Autodesk Fusion 360 part; units mm, degrees
(part 2 of 8)
sketch "B Facet 45 Triangle 2" plane through (0, 53.033, 53.033) normal (0, 0.707107, 0.707107) x (1, 0, 0) in component "B Moving Body"
  line L0 (-43.7939, -27.066) -> (-124, 27.066) construction
  line L1 (-124, 27.066) -> (-124, -27.066) construction
  line L2 (-124, -27.066) -> (-43.7939, -27.066) construction
  line L3 (-56.8709, -23.066) -> (-120, 19.5406)
  line L4 (-120, 19.5406) -> (-120, -23.066)
  line L5 (-120, -23.066) -> (-56.8709, -23.066)
  dimension "d369" = 43.7939
  dimension "d370" = 27.066
  dimension "d371" = 124
  dimension "d372" = 27.066
  dimension "d373" = 124
  dimension "d374" = 27.066
  dimension "d375" = -4
  measures "d369" horizontal distance of origin L0.start
  measures "d370" vertical distance of origin L0.start
  measures "d371" horizontal distance of origin L0.end
  measures "d372" vertical distance of origin L0.end
  measures "d373" horizontal distance of origin L1.end
  measures "d374" vertical distance of origin L1.end
extrude "B Facet 45 Opening 2" cut sketch "B Facet 45 Triangle 2" against normal blind 4.7 bodies 4 in component "B Moving Body"
fillet "B Facet 45 Aperture Root Radii" radius 1.5 6 edges at (-120, 35.1319, 67.7522) (-56.8709, 35.1319, 67.7522) (-120, 65.2593, 37.6247) (-110.9231, 67.7522, 35.1319) (-59.6927, 43.3032, 59.5808) (-84.1416, 67.7522, 35.1319) on bodies 4 in component "B Moving Body"
ref_plane "WorkPlane5" through (12.125, 0, 0) normal (0, 0, 1) x (1, 0, 0) in component "B Moving Body"
ref_plane "WorkPlane6" through (12.125, 0, 75) normal (0, 0, 1) x (1, 0, 0) in component "B Moving Body"
sketch "B Facet 90 Triangle 1" plane through (0, 0, 75) normal (0, 0, 1) x (1, 0, 0) in component "B Moving Body"
  line L0 (17.1665, -27.066) -> (-36.9655, 27.066) construction
  line L1 (-36.9655, 27.066) -> (-53.4167, -27.066) construction
  line L2 (-53.4167, -27.066) -> (17.1665, -27.066) construction
  line L3 (7.5097, -23.066) -> (-35.0777, 19.5214)
  line L4 (-35.0777, 19.5214) -> (-48.0205, -23.066)
  line L5 (-48.0205, -23.066) -> (7.5097, -23.066)
  dimension "d384" = 17.1665
  dimension "d385" = 27.066
  dimension "d386" = 36.9655
  dimension "d387" = 27.066
  dimension "d388" = 53.4167
  dimension "d389" = 27.066
  dimension "d390" = -4
  measures "d384" horizontal distance of origin L0.start
  measures "d385" vertical distance of origin L0.start
  measures "d386" horizontal distance of origin L0.end
  measures "d387" vertical distance of origin L0.end
  measures "d388" horizontal distance of origin L1.end
  measures "d389" vertical distance of origin L1.end
extrude "B Facet 90 Opening 1" cut sketch "B Facet 90 Triangle 1" against normal blind 4.7 bodies 4 in component "B Moving Body"
sketch "B Facet 90 Triangle 2" plane through (0, 0, 75) normal (0, 0, 1) x (1, 0, 0) in component "B Moving Body"
  line L0 (-36.9655, 27.066) -> (-53.4167, -27.066) construction
  line L1 (-53.4167, -27.066) -> (-124, 27.066) construction
  line L2 (-124, 27.066) -> (-36.9655, 27.066) construction
  line L3 (-42.3618, 23.066) -> (-55.5648, -20.3777)
  line L4 (-55.5648, -20.3777) -> (-112.2115, 23.066)
  line L5 (-112.2115, 23.066) -> (-42.3618, 23.066)
  dimension "d393" = 36.9655
  dimension "d394" = 27.066
  dimension "d395" = 53.4167
  dimension "d396" = 27.066
  dimension "d397" = 124
  dimension "d398" = 27.066
  dimension "d399" = 4
  measures "d393" horizontal distance of origin L0.start
  measures "d394" vertical distance of origin L0.start
  measures "d395" horizontal distance of origin L0.end
  measures "d396" vertical distance of origin L0.end
  measures "d397" horizontal distance of origin L1.end
  measures "d398" vertical distance of origin L1.end
extrude "B Facet 90 Opening 2" cut sketch "B Facet 90 Triangle 2" against normal blind 4.7 bodies 4 in component "B Moving Body"
sketch "B Facet 90 Triangle 3" plane through (0, 0, 75) normal (0, 0, 1) x (1, 0, 0) in component "B Moving Body"
  line L0 (-53.4167, -27.066) -> (-124, 27.066) construction
  line L1 (-124, 27.066) -> (-124, -27.066) construction
  line L2 (-124, -27.066) -> (-53.4167, -27.066) construction
  line L3 (-65.2053, -23.066) -> (-120, 18.9574)
  line L4 (-120, 18.9574) -> (-120, -23.066)
  line L5 (-120, -23.066) -> (-65.2053, -23.066)
  dimension "d402" = 53.4167
  dimension "d403" = 27.066
  dimension "d404" = 124
  dimension "d405" = 27.066
  dimension "d406" = 124
  dimension "d407" = 27.066
  dimension "d408" = -4
  measures "d402" horizontal distance of origin L0.start
  measures "d403" vertical distance of origin L0.start
  measures "d404" horizontal distance of origin L0.end
  measures "d405" vertical distance of origin L0.end
  measures "d406" horizontal distance of origin L1.end
  measures "d407" vertical distance of origin L1.end
extrude "B Facet 90 Opening 3" cut sketch "B Facet 90 Triangle 3" against normal blind 4.7 bodies 4 in component "B Moving Body"
fillet "B Facet 90 Aperture Root Radii" radius 1.5 9 edges at (-120, -23.066, 72.75) (-65.2053, -23.066, 72.75) (-120, 18.9574, 72.75) (-112.2115, 23.066, 72.75) (-55.5648, -20.3777, 72.75) (-42.3618, 23.066, 72.75) (-48.0205, -23.066, 72.75) (7.5097, -23.066, 72.75) (-35.0777, 19.5214, 72.75) on bodies 4 in component "B Moving Body"
ref_plane "WorkPlane7" through (12.125, 0, 0) normal (0, -0.707107, 0.707107) x (1, 0, 0) in component "B Moving Body"
ref_plane "WorkPlane8" through (12.125, -53.033, 53.033) normal (0, -0.707107, 0.707107) x (1, 0, 0) in component "B Moving Body"
sketch "B Facet 135 Triangle 1" plane through (0, -53.033, 53.033) normal (0, -0.707107, 0.707107) x (1, 0, 0) in component "B Moving Body"
  line L0 (23.9949, 27.066) -> (62.2721, -27.066) construction
  line L1 (62.2721, -27.066) -> (-25.3367, 27.066) construction
  line L2 (-25.3367, 27.066) -> (23.9949, 27.066) construction
  line L3 (21.9244, 23.066) -> (47.6674, -13.34)
  line L4 (47.6674, -13.34) -> (-11.2532, 23.066)
  line L5 (-11.2532, 23.066) -> (21.9244, 23.066)
  dimension "d417" = 23.9949
  dimension "d418" = 27.066
  dimension "d419" = 62.2721
  dimension "d420" = 27.066
  dimension "d421" = 25.3367
  dimension "d422" = 27.066
  dimension "d423" = 4
  measures "d417" horizontal distance of origin L0.start
  measures "d418" vertical distance of origin L0.start
  measures "d419" horizontal distance of origin L0.end
  measures "d420" vertical distance of origin L0.end
  measures "d421" horizontal distance of origin L1.end
  measures "d422" vertical distance of origin L1.end
extrude "B Facet 135 Opening 1" cut sketch "B Facet 135 Triangle 1" against normal blind 4.7 bodies 4 in component "B Moving Body"
sketch "B Facet 135 Triangle 2" plane through (0, -53.033, 53.033) normal (0, -0.707107, 0.707107) x (1, 0, 0) in component "B Moving Body"
  line L0 (62.2721, -27.066) -> (-25.3367, 27.066) construction
  line L1 (-25.3367, 27.066) -> (-61.9093, -27.066) construction
  line L2 (-61.9093, -27.066) -> (62.2721, -27.066) construction
  line L3 (48.1886, -23.066) -> (-24.1722, 21.6445)
  line L4 (-24.1722, 21.6445) -> (-54.3795, -23.066)
  line L5 (-54.3795, -23.066) -> (48.1886, -23.066)
  dimension "d426" = 62.2721
  dimension "d427" = 27.066
  dimension "d428" = 25.3367
  dimension "d429" = 27.066
  dimension "d430" = 61.9093
  dimension "d431" = 27.066
  dimension "d432" = -4
  measures "d426" horizontal distance of origin L0.start
  measures "d427" vertical distance of origin L0.start
  measures "d428" horizontal distance of origin L0.end
  measures "d429" vertical distance of origin L0.end
  measures "d430" horizontal distance of origin L1.end
  measures "d431" vertical distance of origin L1.end
extrude "B Facet 135 Opening 2" cut sketch "B Facet 135 Triangle 2" against normal blind 4.7 bodies 4 in component "B Moving Body"
sketch "B Facet 135 Triangle 3" plane through (0, -53.033, 53.033) normal (0, -0.707107, 0.707107) x (1, 0, 0) in component "B Moving Body"
  line L0 (-25.3367, 27.066) -> (-61.9093, -27.066) construction
  line L1 (-61.9093, -27.066) -> (-124, 27.066) construction
  line L2 (-124, 27.066) -> (-25.3367, 27.066) construction
  line L3 (-32.8665, 23.066) -> (-62.6909, -21.0779)
  line L4 (-62.6909, -21.0779) -> (-113.325, 23.066)
  line L5 (-113.325, 23.066) -> (-32.8665, 23.066)
  dimension "d435" = 25.3367
  dimension "d436" = 27.066
  dimension "d437" = 61.9093
  dimension "d438" = 27.066
  dimension "d439" = 124
  dimension "d440" = 27.066
  dimension "d441" = 4
  measures "d435" horizontal distance of origin L0.start
  measures "d436" vertical distance of origin L0.start
  measures "d437" horizontal distance of origin L0.end
  measures "d438" vertical distance of origin L0.end
  measures "d439" horizontal distance of origin L1.end
  measures "d440" vertical distance of origin L1.end
extrude "B Facet 135 Opening 3" cut sketch "B Facet 135 Triangle 3" against normal blind 4.7 bodies 4 in component "B Moving Body"
sketch "B Facet 135 Triangle 4" plane through (0, -53.033, 53.033) normal (0, -0.707107, 0.707107) x (1, 0, 0) in component "B Moving Body"
  line L0 (-61.9093, -27.066) -> (-124, 27.066) construction
  line L1 (-124, 27.066) -> (-124, -27.066) construction
  line L2 (-124, -27.066) -> (-61.9093, -27.066) construction
  line L3 (-72.5843, -23.066) -> (-120, 18.272)
  line L4 (-120, 18.272) -> (-120, -23.066)
  line L5 (-120, -23.066) -> (-72.5843, -23.066)
  dimension "d444" = 61.9093
  dimension "d445" = 27.066
  dimension "d446" = 124
  dimension "d447" = 27.066
  dimension "d448" = 124
  dimension "d449" = 27.066
  dimension "d450" = -4
  measures "d444" horizontal distance of origin L0.start
  measures "d445" vertical distance of origin L0.start
  measures "d446" horizontal distance of origin L0.end
  measures "d447" vertical distance of origin L0.end
  measures "d448" horizontal distance of origin L1.end
  measures "d449" vertical distance of origin L1.end
extrude "B Facet 135 Opening 4" cut sketch "B Facet 135 Triangle 4" against normal blind 4.7 bodies 4 in component "B Moving Body"
fillet "B Facet 135 Aperture Root Radii" radius 1.5 12 edges at (-120, -67.7522, 35.1319) (-72.5843, -67.7522, 35.1319) (-120, -38.5218, 64.3623) (-113.325, -35.1319, 67.7522) (-62.6909, -66.3463, 36.5377) (-32.8665, -35.1319, 67.7522) (-54.3795, -67.7522, 35.1319) (48.1886, -67.7522, 35.1319) (-24.1722, -36.137, 66.747) (-11.2532, -35.1319, 67.7522) (47.6674, -60.8748, 42.0092) (21.9244, -35.1319, 67.7522) on bodies 4 in component "B Moving Body"
ref_plane "WorkPlane9" through (12.125, 0, 0) normal (0, -1, 0) x (1, 0, 0) in component "B Moving Body"
ref_plane "WorkPlane10" through (12.125, -75, 0) normal (0, -1, 0) x (1, 0, 0) in component "B Moving Body"
sketch "B Facet 180 Triangle 1" plane through (0, -75, 0) normal (0, -1, 0) x (-1, 0, 0) in component "B Moving Body"
  line L0 (-65.1005, -27.066) -> (-65.1005, 27.066) construction
  line L1 (-65.1005, 27.066) -> (-2.067, -27.066) construction
  line L2 (-2.067, -27.066) -> (-65.1005, -27.066) construction
  line L3 (-61.1005, -23.066) -> (-61.1005, 18.3583)
  line L4 (-61.1005, 18.3583) -> (-12.8644, -23.066)
  line L5 (-12.8644, -23.066) -> (-61.1005, -23.066)
  dimension "d459" = 65.1005
  dimension "d460" = 27.066
  dimension "d461" = 65.1005
  dimension "d462" = 27.066
  dimension "d463" = 2.067
  dimension "d464" = 27.066
  dimension "d465" = 4
  measures "d459" horizontal distance of origin L0.start
  measures "d460" vertical distance of origin L0.start
  measures "d461" horizontal distance of origin L0.end
  measures "d462" vertical distance of origin L0.end
  measures "d463" horizontal distance of origin L1.end
  measures "d464" vertical distance of origin L1.end
extrude "B Facet 180 Opening 1" cut sketch "B Facet 180 Triangle 1" against normal blind 4.7 bodies 4 in component "B Moving Body"
sketch "B Facet 180 Triangle 2" plane through (0, -75, 0) normal (0, -1, 0) x (-1, 0, 0) in component "B Moving Body"
  line L0 (-65.1005, 27.066) -> (-2.067, -27.066) construction
  line L1 (-2.067, -27.066) -> (60.9665, 27.066) construction
  line L2 (60.9665, 27.066) -> (-65.1005, 27.066) construction
  line L3 (-54.3031, 23.066) -> (-2.067, -21.7934)
  line L4 (-2.067, -21.7934) -> (50.1691, 23.066)
  line L5 (50.1691, 23.066) -> (-54.3031, 23.066)
  dimension "d468" = 65.1005
  dimension "d469" = 27.066
  dimension "d470" = 2.067
  dimension "d471" = 27.066
  dimension "d472" = 60.9665
  dimension "d473" = 27.066
  dimension "d474" = -4
  measures "d468" horizontal distance of origin L0.start
  measures "d469" vertical distance of origin L0.start
  measures "d470" horizontal distance of origin L0.end
  measures "d471" vertical distance of origin L0.end
  measures "d472" horizontal distance of origin L1.end
  measures "d473" vertical distance of origin L1.end
extrude "B Facet 180 Opening 2" cut sketch "B Facet 180 Triangle 2" against normal blind 4.7 bodies 4 in component "B Moving Body"
sketch "B Facet 180 Triangle 3" plane through (0, -75, 0) normal (0, -1, 0) x (-1, 0, 0) in component "B Moving Body"
  line L0 (-2.067, -27.066) -> (60.9665, 27.066) construction
  line L1 (60.9665, 27.066) -> (124, -27.066) construction
  line L2 (124, -27.066) -> (-2.067, -27.066) construction
  line L3 (8.7304, -23.066) -> (60.9665, 21.7934)
  line L4 (60.9665, 21.7934) -> (113.2026, -23.066)
  line L5 (113.2026, -23.066) -> (8.7304, -23.066)
  dimension "d477" = 2.067
  dimension "d478" = 27.066
  dimension "d479" = 60.9665
  dimension "d480" = 27.066
  dimension "d481" = 124
  dimension "d482" = 27.066
  dimension "d483" = 4
  measures "d477" horizontal distance of origin L0.start
  measures "d478" vertical distance of origin L0.start
  measures "d479" horizontal distance of origin L0.end
  measures "d480" vertical distance of origin L0.end
  measures "d481" horizontal distance of origin L1.end
  measures "d482" vertical distance of origin L1.end
extrude "B Facet 180 Opening 3" cut sketch "B Facet 180 Triangle 3" against normal blind 4.7 bodies 4 in component "B Moving Body"
sketch "B Facet 180 Triangle 4" plane through (0, -75, 0) normal (0, -1, 0) x (-1, 0, 0) in component "B Moving Body"
  line L0 (60.9665, 27.066) -> (124, -27.066) construction
  line L1 (124, -27.066) -> (124, 27.066) construction
  line L2 (124, 27.066) -> (60.9665, 27.066) construction
  line L3 (71.7639, 23.066) -> (120, -18.3583)
  line L4 (120, -18.3583) -> (120, 23.066)
  line L5 (120, 23.066) -> (71.7639, 23.066)
  dimension "d486" = 60.9665
  dimension "d487" = 27.066
  dimension "d488" = 124
  dimension "d489" = 27.066
  dimension "d490" = 124
  dimension "d491" = 27.066
  dimension "d492" = -4
  measures "d486" horizontal distance of origin L0.start
  measures "d487" vertical distance of origin L0.start
  measures "d488" horizontal distance of origin L0.end
  measures "d489" vertical distance of origin L0.end
  measures "d490" horizontal distance of origin L1.end
  measures "d491" vertical distance of origin L1.end
extrude "B Facet 180 Opening 4" cut sketch "B Facet 180 Triangle 4" against normal blind 4.7 bodies 4 in component "B Moving Body"
fillet "B Facet 180 Aperture Root Radii" radius 1.5 12 edges at (-120, -72.75, -23.066) (-71.7639, -72.75, -23.066) (-120, -72.75, 18.3583) (-113.2026, -72.75, 23.066) (-60.9665, -72.75, -21.7934) (-8.7304, -72.75, 23.066) (-50.1691, -72.75, -23.066) (54.3031, -72.75, -23.066) (2.067, -72.75, 21.7934) (12.8644, -72.75, 23.066) (61.1005, -72.75, -18.3583) (61.1005, -72.75, 23.066) on bodies 4 in component "B Moving Body"
ref_plane "WorkPlane11" through (12.125, 0, 0) normal (0, -0.707107, -0.707107) x (1, 0, 0) in component "B Moving Body"
ref_plane "WorkPlane12" through (12.125, -53.033, -53.033) normal (0, -0.707107, -0.707107) x (1, 0, 0) in component "B Moving Body"
sketch "B Facet 225 Triangle 1" plane through (0, -53.033, -53.033) normal (0, -0.707107, -0.707107) x (1, 0, 0) in component "B Moving Body"
  line L0 (62.2721, 27.066) -> (23.9949, -27.066) construction
  line L1 (23.9949, -27.066) -> (0.1814, 27.066) construction
  line L2 (0.1814, 27.066) -> (62.2721, 27.066) construction
  line L3 (54.5447, 23.066) -> (24.81, -18.9852)
  line L4 (24.81, -18.9852) -> (6.311, 23.066)
  line L5 (6.311, 23.066) -> (54.5447, 23.066)
  dimension "d501" = 62.2721
  dimension "d502" = 27.066
  dimension "d503" = 23.9949
  dimension "d504" = 27.066
  dimension "d505" = 0.1814
  dimension "d506" = 27.066
  dimension "d507" = 4
  measures "d501" horizontal distance of origin L0.start
  measures "d502" vertical distance of origin L0.start
  measures "d503" horizontal distance of origin L0.end
  measures "d504" vertical distance of origin L0.end
  measures "d505" horizontal distance of origin L1.end
  measures "d506" vertical distance of origin L1.end
extrude "B Facet 225 Opening 1" cut sketch "B Facet 225 Triangle 1" against normal blind 4.7 bodies 4 in component "B Moving Body"
sketch "B Facet 225 Triangle 2" plane through (0, -53.033, -53.033) normal (0, -0.707107, -0.707107) x (1, 0, 0) in component "B Moving Body"
  line L0 (23.9949, -27.066) -> (0.1814, 27.066) construction
  line L1 (0.1814, 27.066) -> (-74.6684, -27.066) construction
  line L2 (-74.6684, -27.066) -> (23.9949, -27.066) construction
  line L3 (17.8653, -23.066) -> (-1.4863, 20.9235)
  line L4 (-1.4863, 20.9235) -> (-62.3117, -23.066)
  line L5 (-62.3117, -23.066) -> (17.8653, -23.066)
  dimension "d510" = 23.9949
  dimension "d511" = 27.066
  dimension "d512" = 0.1814
  dimension "d513" = 27.066
  dimension "d514" = 74.6684
  dimension "d515" = 27.066
  dimension "d516" = -4
  measures "d510" horizontal distance of origin L0.start
  measures "d511" vertical distance of origin L0.start
  measures "d512" horizontal distance of origin L0.end
  measures "d513" vertical distance of origin L0.end
  measures "d514" horizontal distance of origin L1.end
  measures "d515" vertical distance of origin L1.end
extrude "B Facet 225 Opening 2" cut sketch "B Facet 225 Triangle 2" against normal blind 4.7 bodies 4 in component "B Moving Body"
sketch "B Facet 225 Triangle 3" plane through (0, -53.033, -53.033) normal (0, -0.707107, -0.707107) x (1, 0, 0) in component "B Moving Body"
  line L0 (0.1814, 27.066) -> (-74.6684, -27.066) construction
  line L1 (-74.6684, -27.066) -> (-124, 27.066) construction
  line L2 (-124, 27.066) -> (0.1814, 27.066) construction
  line L3 (-12.1753, 23.066) -> (-74.1179, -21.7315)
  line L4 (-74.1179, -21.7315) -> (-114.9429, 23.066)
  line L5 (-114.9429, 23.066) -> (-12.1753, 23.066)
  dimension "d519" = 0.1814
  dimension "d520" = 27.066
  dimension "d521" = 74.6684
  dimension "d522" = 27.066
  dimension "d523" = 124
  dimension "d524" = 27.066
  dimension "d525" = 4
  measures "d519" horizontal distance of origin L0.start
  measures "d520" vertical distance of origin L0.start
  measures "d521" horizontal distance of origin L0.end
  measures "d522" vertical distance of origin L0.end
  measures "d523" horizontal distance of origin L1.end
  measures "d524" vertical distance of origin L1.end
extrude "B Facet 225 Opening 3" cut sketch "B Facet 225 Triangle 3" against normal blind 4.7 bodies 4 in component "B Moving Body"
sketch "B Facet 225 Triangle 4" plane through (0, -53.033, -53.033) normal (0, -0.707107, -0.707107) x (1, 0, 0) in component "B Moving Body"
  line L0 (-74.6684, -27.066) -> (-124, 27.066) construction
  line L1 (-124, 27.066) -> (-124, -27.066) construction
  line L2 (-124, -27.066) -> (-74.6684, -27.066) construction
  line L3 (-83.7255, -23.066) -> (-120, 16.7383)
  line L4 (-120, 16.7383) -> (-120, -23.066)
  line L5 (-120, -23.066) -> (-83.7255, -23.066)
  dimension "d528" = 74.6684
  dimension "d529" = 27.066
  dimension "d530" = 124
  dimension "d531" = 27.066
  dimension "d532" = 124
  dimension "d533" = 27.066
  dimension "d534" = -4
  measures "d528" horizontal distance of origin L0.start
  measures "d529" vertical distance of origin L0.start
  measures "d530" horizontal distance of origin L0.end
  measures "d531" vertical distance of origin L0.end
  measures "d532" horizontal distance of origin L1.end
  measures "d533" vertical distance of origin L1.end
extrude "B Facet 225 Opening 4" cut sketch "B Facet 225 Triangle 4" against normal blind 4.7 bodies 4 in component "B Moving Body"
fillet "B Facet 225 Aperture Root Radii" radius 1.5 12 edges at (-120, -35.1319, -67.7522) (-83.7255, -35.1319, -67.7522) (-120, -63.2778, -39.6062) (-114.9429, -67.7522, -35.1319) (-74.1179, -36.0755, -66.8085) (-12.1753, -67.7522, -35.1319) (-62.3117, -35.1319, -67.7522) (17.8653, -35.1319, -67.7522) (-1.4863, -66.2371, -36.6469) (6.311, -67.7522, -35.1319) (24.81, -38.0175, -64.8666) (54.5447, -67.7522, -35.1319) on bodies 4 in component "B Moving Body"
ref_plane "WorkPlane13" through (12.125, 0, 0) normal (0, 0, -1) x (1, 0, 0) in component "B Moving Body"
ref_plane "WorkPlane14" through (12.125, 0, -75) normal (0, 0, -1) x (1, 0, 0) in component "B Moving Body"
sketch "B Facet 270 Triangle 1" plane through (0, 0, -75) normal (0, 0, -1) x (-1, 0, 0) in component "B Moving Body"
  line L0 (-17.1665, -27.066) -> (36.9655, 27.066) construction
  line L1 (36.9655, 27.066) -> (53.4167, -27.066) construction
  line L2 (53.4167, -27.066) -> (-17.1665, -27.066) construction
  line L3 (-7.5097, -23.066) -> (35.0777, 19.5214)
  line L4 (35.0777, 19.5214) -> (48.0205, -23.066)
  line L5 (48.0205, -23.066) -> (-7.5097, -23.066)
  dimension "d543" = 17.1665
  dimension "d544" = 27.066
  dimension "d545" = 36.9655
  dimension "d546" = 27.066
  dimension "d547" = 53.4167
  dimension "d548" = 27.066
  dimension "d549" = 4
  measures "d543" horizontal distance of origin L0.start
  measures "d544" vertical distance of origin L0.start
  measures "d545" horizontal distance of origin L0.end
  measures "d546" vertical distance of origin L0.end
  measures "d547" horizontal distance of origin L1.end
  measures "d548" vertical distance of origin L1.end
extrude "B Facet 270 Opening 1" cut sketch "B Facet 270 Triangle 1" against normal blind 4.7 bodies 4 in component "B Moving Body"
sketch "B Facet 270 Triangle 2" plane through (0, 0, -75) normal (0, 0, -1) x (-1, 0, 0) in component "B Moving Body"
  line L0 (36.9655, 27.066) -> (53.4167, -27.066) construction
  line L1 (53.4167, -27.066) -> (124, 27.066) construction
  line L2 (124, 27.066) -> (36.9655, 27.066) construction
  line L3 (42.3618, 23.066) -> (55.5648, -20.3777)
  line L4 (55.5648, -20.3777) -> (112.2115, 23.066)
  line L5 (112.2115, 23.066) -> (42.3618, 23.066)
  dimension "d552" = 36.9655
  dimension "d553" = 27.066
  dimension "d554" = 53.4167
  dimension "d555" = 27.066
  dimension "d556" = 124
  dimension "d557" = 27.066
  dimension "d558" = -4
  measures "d552" horizontal distance of origin L0.start
  measures "d553" vertical distance of origin L0.start
  measures "d554" horizontal distance of origin L0.end
  measures "d555" vertical distance of origin L0.end
  measures "d556" horizontal distance of origin L1.end
  measures "d557" vertical distance of origin L1.end
extrude "B Facet 270 Opening 2" cut sketch "B Facet 270 Triangle 2" against normal blind 4.7 bodies 4 in component "B Moving Body"
sketch "B Facet 270 Triangle 3" plane through (0, 0, -75) normal (0, 0, -1) x (-1, 0, 0) in component "B Moving Body"
  line L0 (53.4167, -27.066) -> (124, 27.066) construction
  line L1 (124, 27.066) -> (124, -27.066) construction
  line L2 (124, -27.066) -> (53.4167, -27.066) construction
  line L3 (65.2053, -23.066) -> (120, 18.9574)
  line L4 (120, 18.9574) -> (120, -23.066)
  line L5 (120, -23.066) -> (65.2053, -23.066)
  dimension "d561" = 53.4167
  dimension "d562" = 27.066
  dimension "d563" = 124
  dimension "d564" = 27.066
  dimension "d565" = 124
  dimension "d566" = 27.066
  dimension "d567" = 4
  measures "d561" horizontal distance of origin L0.start
  measures "d562" vertical distance of origin L0.start
  measures "d563" horizontal distance of origin L0.end
  measures "d564" vertical distance of origin L0.end
  measures "d565" horizontal distance of origin L1.end
  measures "d566" vertical distance of origin L1.end
extrude "B Facet 270 Opening 3" cut sketch "B Facet 270 Triangle 3" against normal blind 4.7 bodies 4 in component "B Moving Body"
fillet "B Facet 270 Aperture Root Radii" radius 1.5 9 edges at (-120, -23.066, -72.75) (-120, 18.9574, -72.75) (-65.2053, -23.066, -72.75) (-112.2115, 23.066, -72.75) (-42.3618, 23.066, -72.75) (-55.5648, -20.3777, -72.75) (-48.0205, -23.066, -72.75) (-35.0777, 19.5214, -72.75) (7.5097, -23.066, -72.75) on bodies 4 in component "B Moving Body"
ref_plane "WorkPlane15" through (12.125, 0, 0) normal (0, 0.707107, -0.707107) x (1, 0, 0) in component "B Moving Body"
ref_plane "WorkPlane16" through (12.125, 53.033, -53.033) normal (0, 0.707107, -0.707107) x (1, 0, 0) in component "B Moving Body"
sketch "B Facet 315 Triangle 1" plane through (0, 53.033, -53.033) normal (0, 0.707107, -0.707107) x (1, 0, 0) in component "B Moving Body"
  line L0 (-43.7939, 27.066) -> (-82.0711, -27.066) construction
  line L1 (-82.0711, -27.066) -> (-124, 27.066) construction
  line L2 (-124, 27.066) -> (-43.7939, 27.066) construction
  line L3 (-51.5213, 23.066) -> (-82.2175, -20.3449)
  line L4 (-82.2175, -20.3449) -> (-115.8422, 23.066)
  line L5 (-115.8422, 23.066) -> (-51.5213, 23.066)
  dimension "d576" = 43.7939
  dimension "d577" = 27.066
  dimension "d578" = 82.0711
  dimension "d579" = 27.066
  dimension "d580" = 124
  dimension "d581" = 27.066
  dimension "d582" = 4
  measures "d576" horizontal distance of origin L0.start
  measures "d577" vertical distance of origin L0.start
  measures "d578" horizontal distance of origin L0.end
  measures "d579" vertical distance of origin L0.end
  measures "d580" horizontal distance of origin L1.end
  measures "d581" vertical distance of origin L1.end
extrude "B Facet 315 Opening 1" cut sketch "B Facet 315 Triangle 1" against normal blind 4.7 bodies 4 in component "B Moving Body"
sketch "B Facet 315 Triangle 2" plane through (0, 53.033, -53.033) normal (0, 0.707107, -0.707107) x (1, 0, 0) in component "B Moving Body"
  line L0 (-82.0711, -27.066) -> (-124, 27.066) construction
  line L1 (-124, 27.066) -> (-124, -27.066) construction
  line L2 (-124, -27.066) -> (-82.0711, -27.066) construction
  line L3 (-90.2289, -23.066) -> (-120, 15.3697)
  line L4 (-120, 15.3697) -> (-120, -23.066)
  line L5 (-120, -23.066) -> (-90.2289, -23.066)
  dimension "d585" = 82.0711
  dimension "d586" = 27.066
  dimension "d587" = 124
  dimension "d588" = 27.066
  dimension "d589" = 124
  dimension "d590" = 27.066
  dimension "d591" = -4
  measures "d585" horizontal distance of origin L0.start
  measures "d586" vertical distance of origin L0.start
  measures "d587" horizontal distance of origin L0.end
  measures "d588" vertical distance of origin L0.end
  measures "d589" horizontal distance of origin L1.end
  measures "d590" vertical distance of origin L1.end
extrude "B Facet 315 Opening 2" cut sketch "B Facet 315 Triangle 2" against normal blind 4.7 bodies 4 in component "B Moving Body"
fillet "B Facet 315 Aperture Root Radii" radius 1.5 6 edges at (-120, 67.7522, -35.1319) (-90.2289, 67.7522, -35.1319) (-120, 40.574, -62.3101) (-115.8422, 35.1319, -67.7522) (-82.2175, 65.828, -37.056) (-51.5213, 35.1319, -67.7522) on bodies 4 in component "B Moving Body"
ref_plane "WorkPlane17" through (0.3536, 0.3536, 12.125) normal (0.707107, 0.707107, 0) x (0, 0, 1) in component "A Housing"
sketch "A Central Carrier sketch" plane through (0.3536, 0.3536, 0) normal (0.707107, 0.707107, 0) x (0, 0, 1) in component "A Housing"
  circle A0 centre (0, 0) radius 26
  dimension "d598" = 52
  measures "d598" diameter of A0
extrude "A Central Carrier" add sketch "A Central Carrier sketch" along normal blind 18 separate body makes body 5 in component "A Housing"
ref_plane "WorkPlane18" through (0.3536, 0.3536, 12.125) normal (0.707107, 0.707107, 0) x (0, 0, 1) in component "A Housing"
sketch "A Spoke 1 Profile" plane through (0.3536, 0.3536, 0) normal (0.707107, 0.707107, 0) x (0, 0, 1) in component "A Housing"
  line L0 (-4.7984, -1.4054) -> (37.3643, -145.3579)
  line L1 (37.3643, -145.3579) -> (46.9611, -142.547)
  line L2 (46.9611, -142.547) -> (4.7984, 1.4054)
  line L3 (4.7984, 1.4054) -> (-4.7984, -1.4054)
  dimension "d603" = 4.7984
  dimension "d604" = 1.4054
  dimension "d605" = 37.3643
  dimension "d606" = 145.3579
  dimension "d607" = 46.9611
  dimension "d608" = 142.547
  dimension "d609" = 4.7984
  dimension "d610" = 1.4054
  measures "d603" horizontal distance of origin L0.start
  measures "d604" vertical distance of origin L0.start
  measures "d605" horizontal distance of origin L0.end
  measures "d606" vertical distance of origin L0.end
  measures "d607" horizontal distance of origin L1.end
  measures "d608" vertical distance of origin L1.end
  measures "d609" horizontal distance of origin L2.end
  measures "d610" vertical distance of origin L2.end
extrude "A Deep Spoke 1" add sketch "A Spoke 1 Profile" along normal blind 18 bodies 3 5 in component "A Housing"
sketch "A Spoke 2 Profile" plane through (0.3536, 0.3536, 0) normal (0.707107, 0.707107, 0) x (0, 0, 1) in component "A Housing"
  line L0 (-2.5272, -4.3143) -> (126.9012, -80.1317)
  line L1 (126.9012, -80.1317) -> (131.9557, -71.5031)
  line L2 (131.9557, -71.5031) -> (2.5272, 4.3143)
  line L3 (2.5272, 4.3143) -> (-2.5272, -4.3143)
  dimension "d613" = 2.5272
  dimension "d614" = 4.3143
  dimension "d615" = 126.9012
  dimension "d616" = 80.1317
  dimension "d617" = 131.9557
  dimension "d618" = 71.5031
  dimension "d619" = 2.5272
  dimension "d620" = 4.3143
  measures "d613" horizontal distance of origin L0.start
  measures "d614" vertical distance of origin L0.start
  measures "d615" horizontal distance of origin L0.end
  measures "d616" vertical distance of origin L0.end
  measures "d617" horizontal distance of origin L1.end
  measures "d618" vertical distance of origin L1.end
  measures "d619" horizontal distance of origin L2.end
  measures "d620" vertical distance of origin L2.end
extrude "A Deep Spoke 2" add sketch "A Spoke 2 Profile" along normal blind 18 bodies 3 in component "A Housing"
sketch "A Spoke 3 Profile" plane through (0.3536, 0.3536, 0) normal (0.707107, 0.707107, 0) x (0, 0, 1) in component "A Housing"
  line L0 (2.5272, -4.3143) -> (131.9557, 71.5031)
  line L1 (131.9557, 71.5031) -> (126.9012, 80.1317)
  line L2 (126.9012, 80.1317) -> (-2.5272, 4.3143)
  line L3 (-2.5272, 4.3143) -> (2.5272, -4.3143)
  dimension "d623" = 2.5272
  dimension "d624" = 4.3143
  dimension "d625" = 131.9557
  dimension "d626" = 71.5031
  dimension "d627" = 126.9012
  dimension "d628" = 80.1317
  dimension "d629" = 2.5272
  dimension "d630" = 4.3143
  measures "d623" horizontal distance of origin L0.start
  measures "d624" vertical distance of origin L0.start
  measures "d625" horizontal distance of origin L0.end
  measures "d626" vertical distance of origin L0.end
  measures "d627" horizontal distance of origin L1.end
  measures "d628" vertical distance of origin L1.end
  measures "d629" horizontal distance of origin L2.end
  measures "d630" vertical distance of origin L2.end
extrude "A Deep Spoke 3" add sketch "A Spoke 3 Profile" along normal blind 18 bodies 3 in component "A Housing"
sketch "A Spoke 4 Profile" plane through (0.3536, 0.3536, 0) normal (0.707107, 0.707107, 0) x (0, 0, 1) in component "A Housing"
  line L0 (4.7984, -1.4054) -> (46.9611, 142.547)
  line L1 (46.9611, 142.547) -> (37.3643, 145.3579)
  line L2 (37.3643, 145.3579) -> (-4.7984, 1.4054)
  line L3 (-4.7984, 1.4054) -> (4.7984, -1.4054)
  dimension "d633" = 4.7984
  dimension "d634" = 1.4054
  dimension "d635" = 46.9611
  dimension "d636" = 142.547
  dimension "d637" = 37.3643
  dimension "d638" = 145.3579
  dimension "d639" = 4.7984
  dimension "d640" = 1.4054
  measures "d633" horizontal distance of origin L0.start
  measures "d634" vertical distance of origin L0.start
  measures "d635" horizontal distance of origin L0.end
  measures "d636" vertical distance of origin L0.end
  measures "d637" horizontal distance of origin L1.end
  measures "d638" vertical distance of origin L1.end
  measures "d639" horizontal distance of origin L2.end
  measures "d640" vertical distance of origin L2.end
extrude "A Deep Spoke 4" add sketch "A Spoke 4 Profile" along normal blind 18 bodies 3 in component "A Housing"
sketch "A Spoke 5 Profile" plane through (0.3536, 0.3536, 0) normal (0.707107, 0.707107, 0) x (0, 0, 1) in component "A Housing"
  line L0 (4.7984, 1.4054) -> (-37.3643, 145.3579)
  line L1 (-37.3643, 145.3579) -> (-46.9611, 142.547)
  line L2 (-46.9611, 142.547) -> (-4.7984, -1.4054)
  line L3 (-4.7984, -1.4054) -> (4.7984, 1.4054)
  dimension "d643" = 4.7984
  dimension "d644" = 1.4054
  dimension "d645" = 37.3643
  dimension "d646" = 145.3579
  dimension "d647" = 46.9611
  dimension "d648" = 142.547
  dimension "d649" = 4.7984
  dimension "d650" = 1.4054
  measures "d643" horizontal distance of origin L0.start
  measures "d644" vertical distance of origin L0.start
  measures "d645" horizontal distance of origin L0.end
  measures "d646" vertical distance of origin L0.end
  measures "d647" horizontal distance of origin L1.end
  measures "d648" vertical distance of origin L1.end
  measures "d649" horizontal distance of origin L2.end
  measures "d650" vertical distance of origin L2.end
extrude "A Deep Spoke 5" add sketch "A Spoke 5 Profile" along normal blind 18 bodies 3 in component "A Housing"
sketch "A Spoke 6 Profile" plane through (0.3536, 0.3536, 0) normal (0.707107, 0.707107, 0) x (0, 0, 1) in component "A Housing"
  line L0 (2.5272, 4.3143) -> (-126.9012, 80.1317)
  line L1 (-126.9012, 80.1317) -> (-131.9557, 71.5031)
  line L2 (-131.9557, 71.5031) -> (-2.5272, -4.3143)
  line L3 (-2.5272, -4.3143) -> (2.5272, 4.3143)
  dimension "d653" = 2.5272
  dimension "d654" = 4.3143
  dimension "d655" = 126.9012
  dimension "d656" = 80.1317
  dimension "d657" = 131.9557
  dimension "d658" = 71.5031
  dimension "d659" = 2.5272
  dimension "d660" = 4.3143
  measures "d653" horizontal distance of origin L0.start
  measures "d654" vertical distance of origin L0.start
  measures "d655" horizontal distance of origin L0.end
  measures "d656" vertical distance of origin L0.end
  measures "d657" horizontal distance of origin L1.end
  measures "d658" vertical distance of origin L1.end
  measures "d659" horizontal distance of origin L2.end
  measures "d660" vertical distance of origin L2.end
extrude "A Deep Spoke 6" add sketch "A Spoke 6 Profile" along normal blind 18 bodies 3 in component "A Housing"
sketch "A Spoke 7 Profile" plane through (0.3536, 0.3536, 0) normal (0.707107, 0.707107, 0) x (0, 0, 1) in component "A Housing"
  line L0 (-2.5272, 4.3143) -> (-131.9557, -71.5031)
  line L1 (-131.9557, -71.5031) -> (-126.9012, -80.1317)
  line L2 (-126.9012, -80.1317) -> (2.5272, -4.3143)
  line L3 (2.5272, -4.3143) -> (-2.5272, 4.3143)
  dimension "d663" = 2.5272
  dimension "d664" = 4.3143
  dimension "d665" = 131.9557
  dimension "d666" = 71.5031
  dimension "d667" = 126.9012
  dimension "d668" = 80.1317
  dimension "d669" = 2.5272
  dimension "d670" = 4.3143
  measures "d663" horizontal distance of origin L0.start
  measures "d664" vertical distance of origin L0.start
  measures "d665" horizontal distance of origin L0.end
  measures "d666" vertical distance of origin L0.end
  measures "d667" horizontal distance of origin L1.end
  measures "d668" vertical distance of origin L1.end
  measures "d669" horizontal distance of origin L2.end
  measures "d670" vertical distance of origin L2.end
extrude "A Deep Spoke 7" add sketch "A Spoke 7 Profile" along normal blind 18 bodies 3 in component "A Housing"
sketch "A Spoke 8 Profile" plane through (0.3536, 0.3536, 0) normal (0.707107, 0.707107, 0) x (0, 0, 1) in component "A Housing"
  line L0 (-4.7984, 1.4054) -> (-46.9611, -142.547)
  line L1 (-46.9611, -142.547) -> (-37.3643, -145.3579)
  line L2 (-37.3643, -145.3579) -> (4.7984, 1.4054)
  line L3 (4.7984, 1.4054) -> (-4.7984, 1.4054)
  dimension "d673" = 4.7984
  dimension "d674" = 1.4054
  dimension "d675" = 46.9611
  dimension "d676" = 142.547
  dimension "d677" = 37.3643
  dimension "d678" = 145.3579
  dimension "d679" = 4.7984
  dimension "d680" = 1.4054
  measures "d673" horizontal distance of origin L0.start
  measures "d674" vertical distance of origin L0.start
  measures "d675" horizontal distance of origin L0.end
  measures "d676" vertical distance of origin L0.end
  measures "d677" horizontal distance of origin L1.end
  measures "d678" vertical distance of origin L1.end
  measures "d679" horizontal distance of origin L2.end
  measures "d680" vertical distance of origin L2.end
extrude "A Deep Spoke 8" add sketch "A Spoke 8 Profile" along normal blind 18 bodies 3 in component "A Housing"
sketch "Spoke Outer Envelope" plane through (0, 0, 0) normal (1, 0, 0) x (0, 0, -1) in component "A Housing"
  line L0 (75, 31.066) -> (31.066, 75)
  line L1 (31.066, 75) -> (-31.066, 75)
  line L2 (-31.066, 75) -> (-75, 31.066)
  line L3 (-75, 31.066) -> (-75, -31.066)
  line L4 (-75, -31.066) -> (-31.066, -75)
  line L5 (-31.066, -75) -> (31.066, -75)
  line L6 (31.066, -75) -> (75, -31.066)
  line L7 (75, -31.066) -> (75, 31.066)
  dimension "d683" = 150
  constraint horizontal L1
  measures "d683" vertical distance of L0.end L5.end